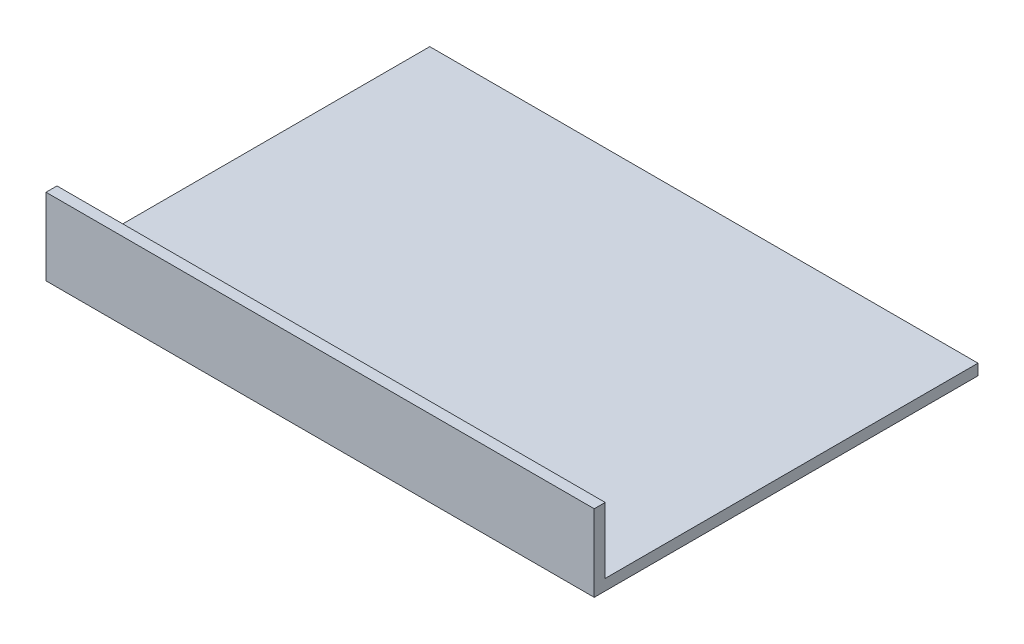
# Autodesk Inventor part: RDS-GHN500-1001 Container shelf
Saved by Autodesk Inventor 2026 (Build 300175000, 175)
## iProperties
Created: 2026-10-27
Part Number: RDS-GHN500-1001 Container shelf
Material: Типовые
Document SubType Name: Modeling
Designer: user
Density: 1 g/cm^3
Appearance: По умолчанию
Author: user
Autodesk Inventor part; units mm, degrees
ref_plane "YZ Plane" through (0, 0, 0) normal (1, 0, 0) x (0, 1, 0)
ref_plane "XZ Plane" through (0, 0, 0) normal (0, 1, 0) x (-1, 0, 0)
ref_plane "XY Plane" through (0, 0, 0) normal (0, 0, 1) x (1, 0, 0)
sketch "Эскиз1" plane through (0, 0, 0) normal (1, 0, 0) x (0, 1, 0)
  line L0 (0, 0) -> (0, 350)
  line L1 (0, 350) -> (70, 350)
  line L2 (70, 350) -> (70, 340)
  line L3 (70, 340) -> (10, 340)
  line L4 (10, 340) -> (10, 0)
  line L5 (10, 0) -> (0, 0)
  dimension "d0" = 350
  dimension "d1" = 70
  dimension "d2" = 10
  dimension "d3" = 60
  dimension "d4" = 340
  constraints: 12 end point, 4 perpendicular, 1 vertical
  measures "d0" distance of L0.start L0.end
  measures "d1" distance of L0.end L1.end
  measures "d2" distance of L1.end L2.end
  measures "d3" distance of L2.end L3.end
  measures "d4" distance of L3.end L4.end
extrude "Выдавливание1" add sketch "Эскиз1" against normal blind 500
